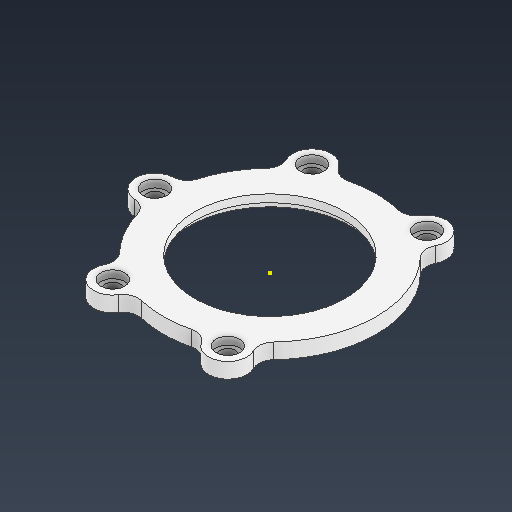
# Autodesk Inventor part: case_s
Saved by Autodesk Inventor 2026.2 (Build 302298010, 298A)
## iProperties
Created: 2026-04-10
Part Number: case_s
Material: PLA
Document SubType Name: Modeling
Designer: khw
Density: 1.24 g/cm^3
Appearance: 일반
Author: khw
Autodesk Inventor part; units mm, degrees
ref_plane "YZ Plane" through (0, 0, 0) normal (1, 0, 0) x (0, 1, 0)
ref_plane "XZ Plane" through (0, 0, 0) normal (0, 1, 0) x (-1, 0, 0)
ref_plane "XY Plane" through (0, 0, 0) normal (0, 0, 1) x (1, 0, 0)
sketch "스케치1" plane through (0, 0, 0) normal (0, 1, 0) x (-1, 0, 0)
  circle A0 centre (0, 0) radius 19.6
  circle A1 centre (0, 0) radius 27.75
  line L0 (0, 0) -> (30, 0) construction
  circle A2 centre (30, 0) radius 5
  circle A3 centre (15, 25.9808) radius 5
  line L1 (0, 0) -> (15, 25.9808) construction
  circle A4 centre (-15, 25.9808) radius 5
  line L2 (0, 0) -> (-15, 25.9808) construction
  circle A5 centre (-30, 0) radius 5
  line L3 (0, 0) -> (-30, 0) construction
  circle A6 centre (-15, -25.9808) radius 5
  line L4 (0, 0) -> (-15, -25.9808) construction
  circle A7 centre (15, -25.9808) radius 5
  line L5 (0, 0) -> (15, -25.9808) construction
  point P0 (17.4168, 21.6037)
  point P1 (10.0009, 25.8852)
  point P2 (-10.0009, 25.8852)
  point P3 (-17.4168, 21.6037)
  point P4 (-17.4168, -21.6037)
  point P5 (-10.0009, -25.8852)
  point P6 (10.0009, -25.8852)
  point P7 (17.4168, -21.6037)
  point P8 (27.4177, -4.2816)
  point P9 (27.4177, 4.2816)
  dimension "d0" = 39.2
  dimension "d1" = 55.5
  dimension "d2" = 30
  dimension "d3" = 10
  dimension "d6" = 360
  constraints: 12 end point, 10 coincident, 8 centre point, 1 horizontal, 29 other
  measures "d0" diameter of A0
  measures "d1" diameter of A1
  measures "d2" distance of L0.start L0.end
  measures "d3" diameter of A2
extrude "돌출1" add sketch "스케치1" along normal blind 4 contours A1 A2 | A1 A2 | A2 A1 A7 A6 A5 A4 A3 | A3 A1 | A1 A3 | A7 A1 | A1 A7 | A4 A1 | A1 A4 | A6 A1 | A1 A6 | A5 A1 picked at (-26.8087, 0)
fillet "모깎기1" radius 4 10 edges at (-27.4177, 2, -4.2816) (-27.4177, 2, 4.2816) (10.0009, 2, 25.8852) (-17.4168, 2, 21.6037) (-10.0009, 2, 25.8852) (17.4168, 2, 21.6037) (-17.4168, 2, -21.6037) (-10.0009, 2, -25.8852) (17.4168, 2, -21.6037) (10.0009, 2, -25.8852)
sketch "스케치2" plane through (0, 4, 0) normal (0, 1, 0) x (1, 0, 0)
  arc A0 (-6.5036, -26.9771) -> (6.5036, -26.9771) centre (0, 0) ccw projected
  arc A1 (10.8006, -28.6946) -> (6.5036, -26.9771) centre (7.4411, -30.8657) ccw projected
  arc A2 (10.8006, -28.6946) -> (19.45, -23.7009) centre (15, -25.9808) ccw projected
  arc A3 (20.1111, -19.1209) -> (19.45, -23.7009) centre (23.01, -21.877) ccw projected
  arc A4 (20.1111, -19.1209) -> (20.1111, 19.1209) centre (0, 0) ccw projected
  arc A5 (19.45, 23.7009) -> (20.1111, 19.1209) centre (23.01, 21.877) ccw projected
  arc A6 (19.45, 23.7009) -> (10.8006, 28.6946) centre (15, 25.9808) ccw projected
  arc A7 (6.5036, 26.9771) -> (10.8006, 28.6946) centre (7.4411, 30.8657) ccw projected
  arc A8 (6.5036, 26.9771) -> (-6.5036, 26.9771) centre (0, 0) ccw projected
  arc A9 (-10.8006, 28.6946) -> (-6.5036, 26.9771) centre (-7.4411, 30.8657) ccw projected
  arc A10 (-10.8006, 28.6946) -> (-19.45, 23.7009) centre (-15, 25.9808) ccw projected
  arc A11 (-20.1111, 19.1209) -> (-19.45, 23.7009) centre (-23.01, 21.877) ccw projected
  arc A12 (-20.1111, 19.1209) -> (-26.6147, 7.8563) centre (0, 0) ccw projected
  arc A13 (-30.2506, 4.9937) -> (-26.6147, 7.8563) centre (-30.451, 8.9887) ccw projected
  arc A14 (-30.2506, 4.9937) -> (-30.2506, -4.9937) centre (-30, 0) ccw projected
  arc A15 (-26.6147, -7.8563) -> (-30.2506, -4.9937) centre (-30.451, -8.9887) ccw projected
  arc A16 (-26.6147, -7.8563) -> (-20.1111, -19.1209) centre (0, 0) ccw projected
  arc A17 (-19.45, -23.7009) -> (-20.1111, -19.1209) centre (-23.01, -21.877) ccw projected
  arc A18 (-19.45, -23.7009) -> (-10.8006, -28.6946) centre (-15, -25.9808) ccw projected
  arc A19 (-6.5036, -26.9771) -> (-10.8006, -28.6946) centre (-7.4411, -30.8657) ccw projected
  circle A20 centre (0, 0) radius 19.6 projected
  constraints: 5 coincident
hole "구멍1" at (-15, 4, 25.9808) at (15, 4, 25.9808) at (15, 4, -25.9808) at (-15, 4, -25.9808) at (-30, 4, 0) direction (0, -1, 0) diameter 4 end through all counterbore diameter 6.2 counterbore depth 2
sketch "스케치3" plane through (0, 0, 0) normal (0, -1, 0) x (1, 0, 0)
  point P0 (0, 0)
sketch "스케치4" plane through (0, 0, 0) normal (0, -1, 0) x (1, 0, 0)
  circle A0 centre (0, 0) radius 21.1
  dimension "d18" = 42.2
  constraints: 1 centre point, 1 coincident
  measures "d18" diameter of A0
extrude "돌출2" cut sketch "스케치4" against normal blind 2
